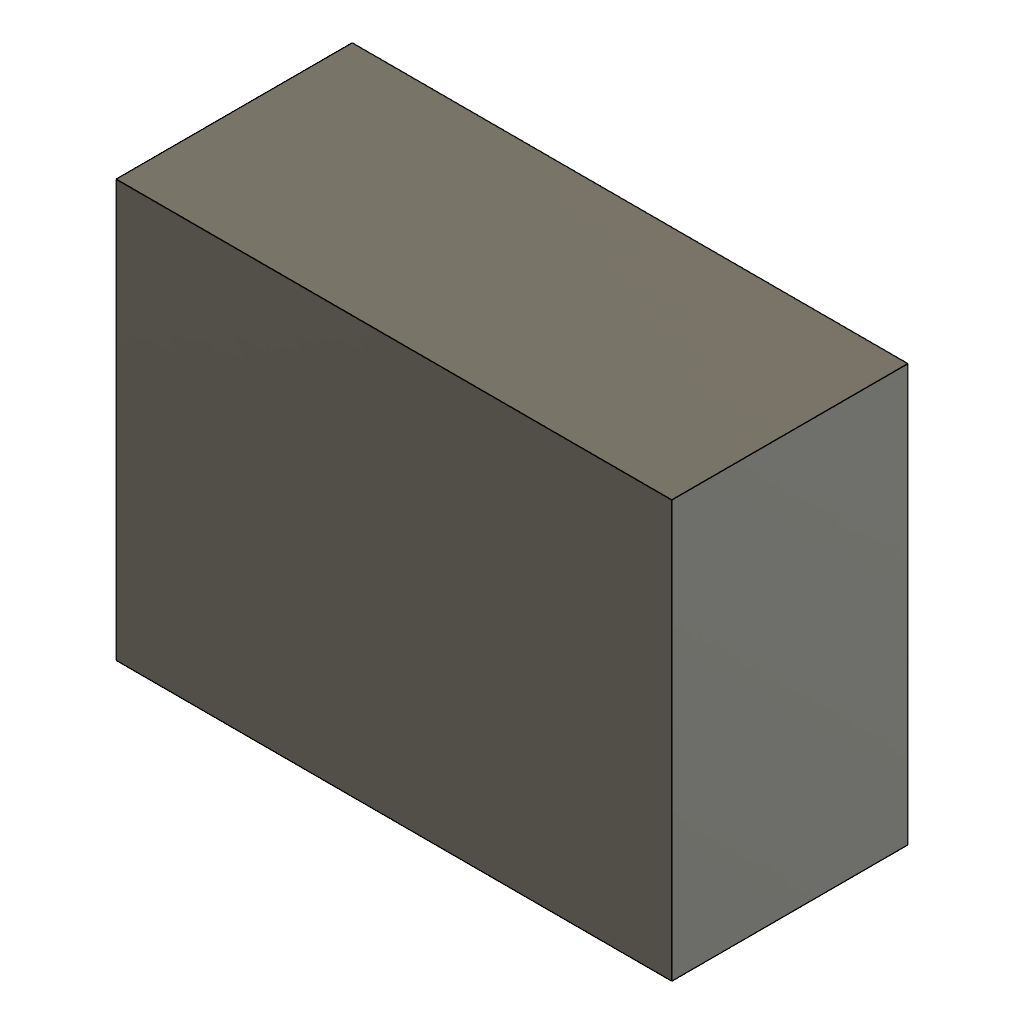
TopNegative (Autodesk Fusion 360 design; units mm, degrees)
part number: 2026-11-22-13-36-48-286
Autodesk Fusion 360 part; units mm, degrees
sketch "Base sketch" plane through (0, 0, 0) normal (0, 0, 1) x (1, 0, 0)
  line L0 (0, 0) -> (40, 0)
  line L1 (40, 0) -> (40, 30)
  line L2 (40, 30) -> (0, 30)
  line L3 (0, 30) -> (0, 0)
extrude "Base" add sketch "Base sketch" along normal blind 20
move_face "Measured face offset" offset -3 1 faces at (13.3333, 20, 20)
